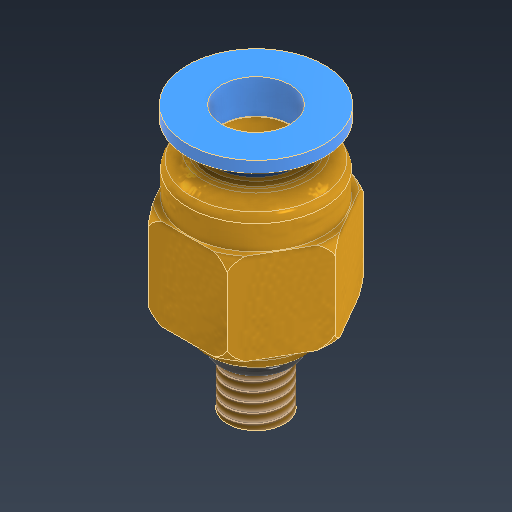
# Autodesk Inventor part: PC6-M5
Saved by Autodesk Inventor 2026.2 (Build 302298010, 298A)
## iProperties
Created: 2026-04-30
Part Number: PC6-M5
Material: 황동, 연질 노란색, 용접
Document SubType Name: Modeling
Designer: khw
Density: 8.5 g/cm^3
Appearance: 용접 - 황동
Author: khw
Autodesk Inventor part; units mm, degrees
ref_plane "YZ Plane" through (0, 0, 0) normal (1, 0, 0) x (0, 1, 0)
ref_plane "XZ Plane" through (0, 0, 0) normal (0, 1, 0) x (-1, 0, 0)
sketch "스케치1" plane through (0, 0, 0) normal (0, 1, 0) x (-1, 0, 0)
  circle A0 centre (0, 0) radius 2.5
  dimension "d0" = 5
  constraints: 1 centre point, 1 coincident
  measures "d0" diameter of A0
extrude "돌출1" add sketch "스케치1" along normal blind 5
sketch "스케치2" plane through (0, 0, 0) normal (1, 0, 0) x (0, 1, 0)
  line L0 (0, 0) -> (8, 0)
  line L1 (8, 0) -> (8, -4.5)
  line L2 (5, -2.5) -> (5, 2.5) projected
  line L3 (5, -2.5) -> (6.1547, -4.5)
  line L4 (6.1547, -4.5) -> (8, -4.5)
  point P0 (5, 0)
  point P1 (7.0774, -4.5)
  dimension "d3" = 3
  dimension "d5" = 150
  dimension "d19" = 9
  constraints: 8 end point, 2 perpendicular, 1 horizontal, 1 midpoint
  measures "d3" distance between parallel lines of L1 L2
  measures "d5" angle of L2 L3
  measures "d19" diameter of point (7.077, -4.5) L0
revolve "회전1" add sketch "스케치2" angle 360 about axis through (0, 0, 0) along (0, 1, 0)
sketch "스케치3" plane through (0, 8, 0) normal (0, 1, 0) x (1, 0, 0)
  line L0 (-6.9282, 0) -> (-3.4641, 6)
  line L1 (-3.4641, 6) -> (3.4641, 6)
  line L2 (3.4641, 6) -> (6.9282, 0)
  line L3 (6.9282, 0) -> (3.4641, -6)
  line L4 (3.4641, -6) -> (-3.4641, -6)
  line L5 (-3.4641, -6) -> (-6.9282, 0)
  line L6 (0, 0) -> (-6.9282, 0) construction
  dimension "d7" = 12
  constraints: 14 end point, 1 coincident, 1 horizontal, 13 other
  measures "d7" distance between parallel lines of L2 L5
extrude "돌출2" add sketch "스케치3" along normal blind 8
ref_plane "작업 평면1" through (0, 12, 0) normal (0, 1, 0) x (1, 0, 0)
sketch "스케치7" plane through (0, 0, 0) normal (0, 0, 1) x (1, 0, 0)
  line L0 (-3.4641, 8) -> (3.4641, 8) projected
  line L1 (3.4641, 8) -> (3.4641, 16) projected
  line L2 (-3.4641, 16) -> (3.4641, 16) projected
  line L3 (-3.4641, 8) -> (-3.4641, 16) projected
  line L4 (-3.4641, 16) -> (3.4641, 16) projected
  line L5 (0, 16) -> (0, 20)
  line L6 (0, 20) -> (4, 20)
  line L7 (4, 20) -> (4, 19.6)
  line L8 (4, 19.6) -> (4.4, 19.6)
  arc A0 (5.9282, 18.5) -> (4.4, 19.6) centre (3.5, 16.7382) ccw
  line L9 (3.4641, 16) -> (6.9282, 16) projected
  line L10 (5.9282, 18.5) -> (5.9282, 16)
  line L11 (3, 20) -> (3, 23)
  line L12 (3, 23) -> (0, 23) construction
  line L13 (3.6, 20) -> (3.6, 22)
  line L14 (3.6, 22) -> (6, 22)
  line L15 (6, 22) -> (6, 23)
  line L16 (6, 23) -> (3, 23)
  line L17 (0, 20) -> (0, 23) construction
  point P0 (0, 0)
  point P1 (2, 20)
  dimension "d27" = 0.4
  dimension "d28" = 4
  dimension "d29" = 0.4
  dimension "d30" = 3
  dimension "d31" = 4
  dimension "d32" = 1
  dimension "d33" = 2.5
  dimension "d34" = 6
  dimension "d35" = 3
  dimension "d36" = 1
  dimension "d37" = 0.4
  dimension "d38" = 12
  constraints: 24 end point, 8 perpendicular, 4 vertical, 3 point on line, 2 midpoint, 2 point on circle, 1 centre point
  measures "d27" distance of L6.end L7.end
  measures "d28" distance of L5.end L6.end
  measures "d29" distance of L7.end L8.end
  measures "d30" radius of A0
  measures "d31" distance from line of L2 point (2, 20)
  measures "d32" distance from line of L9.end L10
  measures "d33" distance of L10.end L10.start
  measures "d34" diameter of L11 L5
  measures "d35" distance between parallel lines of L6 L12
  measures "d36" distance between parallel lines of L16 L14
  measures "d37" distance from line of L6.end L13
  measures "d38" diameter of L15 L5
revolve "회전4" add sketch "스케치7" angle 360 about axis through (0, 16, 0) along (0, 1, 0) contours L2 L5 L6 L7 L8 A0 L10 L9 | L11 L16 L15 L14 L13 L6
sketch "스케치8" plane through (0, 20, 0) normal (0, 1, 0) x (1, 0, 0)
  circle A0 centre (0, 0) radius 2.9358
  constraints: 1 centre point, 1 coincident
extrude "돌출3" cut sketch "스케치8" against normal up to surface (12 mm away)
sketch "스케치9" plane through (0, 0, 0) normal (0, -1, 0) x (1, 0, 0)
  circle A0 centre (0, 0) radius 1.5
  dimension "d42" = 3
  constraints: 1 centre point, 1 coincident
  measures "d42" diameter of A0
extrude "돌출4" cut sketch "스케치9" against normal blind 10
thread "스레드1" size "M5x0.8" class "6g" standard "ISO Metric profile" full length
sketch "스케치10" plane through (0, 0, 0) normal (1, 0, 0) x (0, 1, 0)
  circle A0 centre (4.8, -2.8) radius 0.375
  line L0 (5, -2.5) -> (5, 2.5) projected
  line L1 (0, 0) -> (5, 0)
  dimension "d47" = 0.75
  dimension "d48" = 0.2
  dimension "d49" = 0.3
  constraints: 2 end point, 1 centre point, 1 midpoint
  measures "d47" diameter of A0
  measures "d48" distance from line of L0 A0.centre
  measures "d49" vertical distance of L0.start A0.centre
revolve "회전5" add sketch "스케치10" angle 360 about axis through (0, 0, 0) along (0, 1, 0)
sketch "스케치11" plane through (0, 0, 0) normal (0, 0, 1) x (1, 0, 0)
  line L0 (6.9282, 16) -> (3.4641, 16) projected
  arc A0 (6.9282, 15) -> (6.4282, 16) centre (4.0419, 14.1819) ccw
  line L1 (6.9282, 8) -> (3.4641, 8) projected
  line L2 (3.4641, 8) -> (3.4641, 16) projected
  line L3 (6.9282, 16) -> (3.4641, 16) projected
  line L4 (6.9282, 8) -> (6.9282, 16) projected
  line L5 (6.9282, 12) -> (3.4641, 12) construction
  line L6 (6, 23) -> (-6, 23) projected
  line L7 (0, 23) -> (0, 0)
  arc A1 (6.4282, 8) -> (6.9282, 9) centre (4.0419, 9.8181) ccw
  point P0 (6.9282, 9)
  point P1 (6.4282, 8)
  dimension "d51" = 1
  dimension "d52" = 0.5
  dimension "d53" = 3
  constraints: 4 end point, 4 point on circle, 3 midpoint, 3 symmetric about line, 2 centre point, 2 point on line, 1 perpendicular, 1 vertical, 1 other
  measures "d51" distance of A0.start L0.start
  measures "d52" distance of L0.start A0.end
  measures "d53" radius of A0
revolve "회전6" cut sketch "스케치11" angle 360 about axis through (0, 23, 0) along (0, -1, 0) contours L4 A0 L0 | L4 L1 A1
fillet "모깎기1" radius 1 3 edges at (-5.9282, 18.5, 0) (-4.4, 19.6, 0) (0, 6.1547, 4.5)
